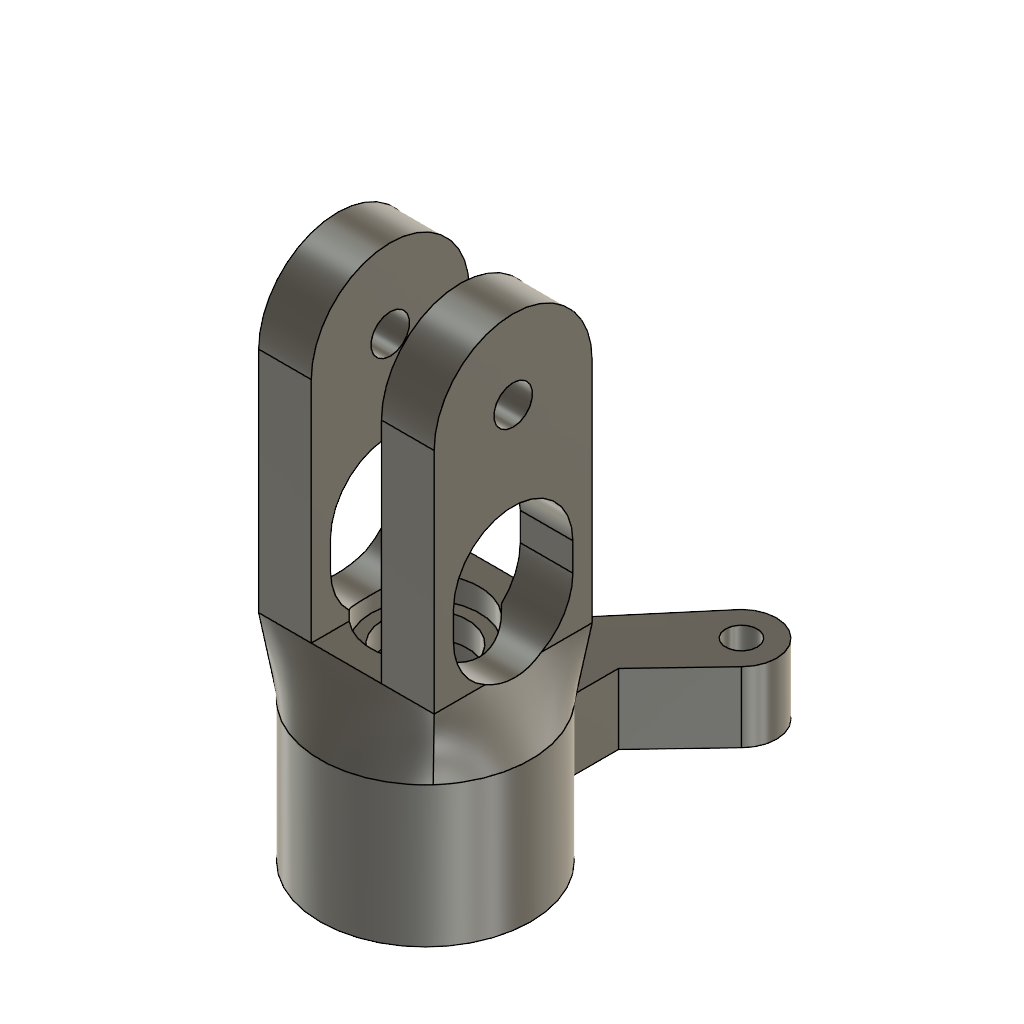
grip-r7-fit-only (Autodesk Fusion 360 design; units mm, degrees)
part number: 2026-11-01-15-01-52-931
Autodesk Fusion 360 part; units mm, degrees
ref_plane "WorkPlane1" through (0, 0, 0) normal (0, 0, 1) x (1, 0, 0)
sketch "Compact round bearing housing" plane through (0, 0, 0) normal (0, 0, 1) x (1, 0, 0)
  circle A0 centre (0, 0) radius 6
extrude "Compact round bearing housing (1)" add sketch "Compact round bearing housing" along normal blind 8
ref_plane "WorkPlane2" through (0, 0, 8) normal (0, 0, 1) x (1, 0, 0)
sketch "Round transition start" plane through (0, 0, 8) normal (0, 0, 1) x (1, 0, 0)
  circle A0 centre (0, 0) radius 6
ref_plane "WorkPlane3" through (0, 0, 12) normal (0, 0, 1) x (1, 0, 0)
sketch "Slim fork transition end" plane through (0, 0, 12) normal (0, 0, 1) x (1, 0, 0)
  line L0 (-5, -4.5) -> (5, -4.5)
  line L1 (5, -4.5) -> (5, 4.5)
  line L2 (5, 4.5) -> (-5, 4.5)
  line L3 (-5, 4.5) -> (-5, -4.5)
loft "Continuous housing to fork transition" add profiles "Round transition start", "Slim fork transition end" section 1 section 2
ref_plane "WorkPlane4" through (-5, 0, 0) normal (1, 0, 0) x (0, 1, 0)
sketch "Rounded slim fork A - provisional blade fit" plane through (-5, 0, 0) normal (1, 0, 0) x (0, 0, -1)
  line L0 (-12, -4.5) -> (-12, 4.5)
  line L1 (-12, 4.5) -> (-25, 4.5)
  arc A0 (-25, 4.5) -> (-25, -4.5) centre (-25, 0) ccw
  line L2 (-25, -4.5) -> (-12, -4.5)
extrude "Rounded slim fork A - provisional blade fit (1)" add sketch "Rounded slim fork A - provisional blade fit" along normal blind 3
ref_plane "WorkPlane5" through (2, 0, 0) normal (1, 0, 0) x (0, 1, 0)
sketch "Rounded slim fork B - provisional blade fit" plane through (2, 0, 0) normal (1, 0, 0) x (0, 0, -1)
  line L0 (-12, -4.5) -> (-12, 4.5)
  line L1 (-12, 4.5) -> (-25, 4.5)
  arc A0 (-25, 4.5) -> (-25, -4.5) centre (-25, 0) ccw
  line L2 (-25, -4.5) -> (-12, -4.5)
extrude "Rounded slim fork B - provisional blade fit (1)" add sketch "Rounded slim fork B - provisional blade fit" along normal blind 3
ref_plane "WorkPlane6" through (0, 0, 2) normal (0, 0, 1) x (1, 0, 0)
sketch "Angled pitch control arm" plane through (0, 0, 2) normal (0, 0, 1) x (1, 0, 0)
  line L0 (-2, 4) -> (2, 4)
  line L1 (2, 4) -> (2, 9)
  line L2 (2, 9) -> (5.4142, 12.5858)
  arc A0 (5.4142, 12.5858) -> (2.5858, 15.4142) centre (4, 14) ccw
  line L3 (2.5858, 15.4142) -> (-2, 10)
  line L4 (-2, 10) -> (-2, 4)
extrude "Integral angled pitch arm" add sketch "Angled pitch control arm" along normal blind 4
ref_plane "WorkPlane7" through (0, 0, 0) normal (0, 0, 1) x (1, 0, 0)
sketch "Internal shoulder relief assumed" plane through (0, 0, 0) normal (0, 0, 1) x (1, 0, 0)
  circle A0 centre (0, 0) radius 2.4
extrude "Internal shoulder relief assumed (1)" cut sketch "Internal shoulder relief assumed" along normal blind 12
ref_plane "WorkPlane8" through (0, 0, 0) normal (0, 0, 1) x (1, 0, 0)
sketch "Bottom-loaded complete bearing stack pocket" plane through (0, 0, 0) normal (0, 0, 1) x (1, 0, 0)
  circle A0 centre (0, 0) radius 3.075
extrude "Bottom-loaded complete bearing stack pocket (1)" cut sketch "Bottom-loaded complete bearing stack pocket" along normal blind 9.3
ref_plane "WorkPlane9" through (0, 0, 10.7) normal (0, 0, 1) x (1, 0, 0)
sketch "Relief beyond terminal retaining shoulder" plane through (0, 0, 10.7) normal (0, 0, 1) x (1, 0, 0)
  circle A0 centre (0, 0) radius 3.075
extrude "Relief beyond terminal retaining shoulder (1)" cut sketch "Relief beyond terminal retaining shoulder" along normal blind 6.9
sketch "Oval bearing assembly access" plane through (0, 0, 0) normal (1, 0, 0) x (0, 0, -1)
  line L0 (-15, 3.4) -> (-16.6, 3.4)
  arc A0 (-16.6, 3.4) -> (-16.6, -3.4) centre (-16.6, 0) ccw
  line L1 (-16.6, -3.4) -> (-15, -3.4)
  arc A1 (-15, -3.4) -> (-15, 3.4) centre (-15, 0) ccw
extrude "Oval assembly access through both cheeks" cut sketch "Oval bearing assembly access" along normal mid plane 40
sketch "Blade bolt 2.2 mm assumed" plane through (0, 0, 0) normal (1, 0, 0) x (0, 0, -1)
  circle A0 centre (-25, 0) radius 1.1
extrude "Extrude9" cut sketch "Blade bolt 2.2 mm assumed" along normal mid plane 40
ref_plane "WorkPlane10" through (0, 0, 2) normal (0, 0, 1) x (1, 0, 0)
sketch "Pitch ball mounting 1.8 mm assumed" plane through (0, 0, 2) normal (0, 0, 1) x (1, 0, 0)
  circle A0 centre (4, 14) radius 0.9
extrude "Extrude10" cut sketch "Pitch ball mounting 1.8 mm assumed" along normal blind 4
named bodies: "PETG grip - fit prototype only"
